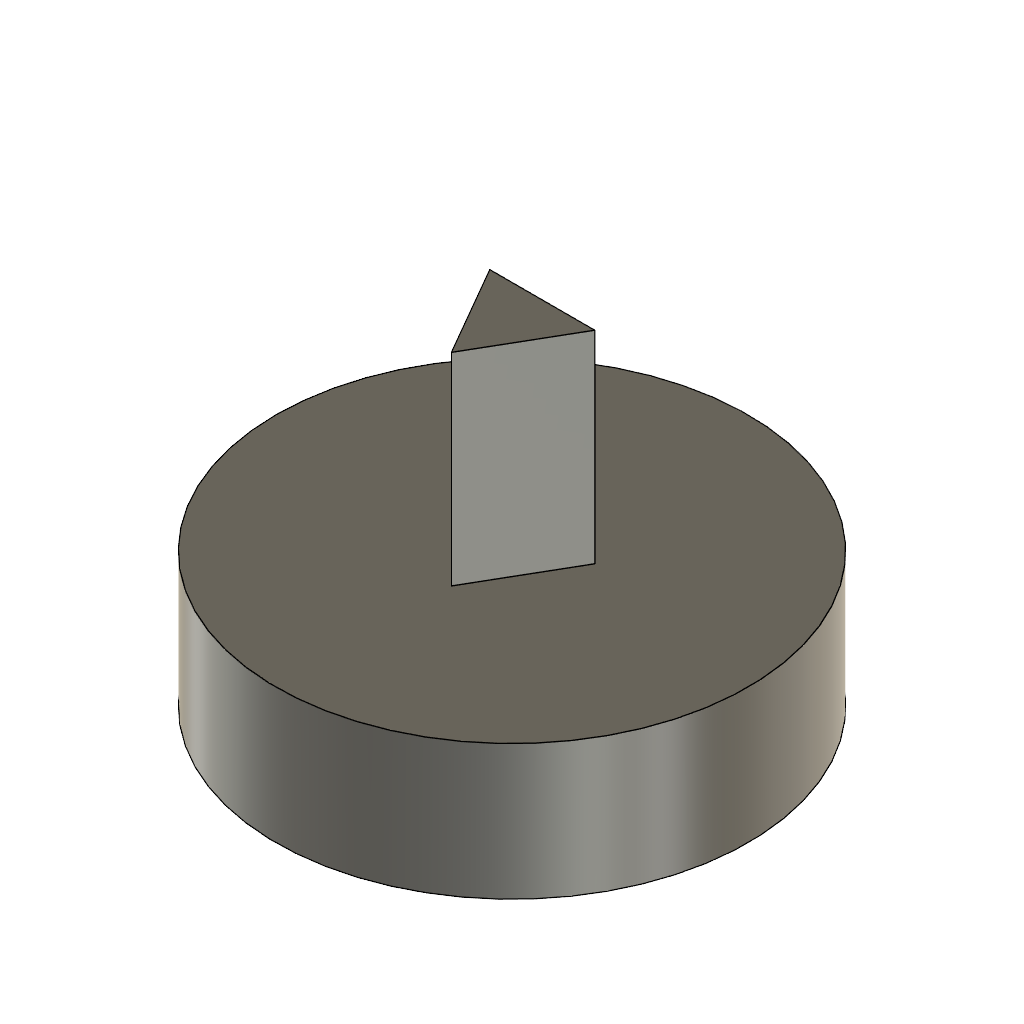
WheelCap (Autodesk Fusion 360 design; units mm, degrees)
part number: 2026-10-10-16-35-32-340
Autodesk Fusion 360 part; units mm, degrees
sketch "Szkic1" plane through (0, 0, 0) normal (0, 0, 1) x (1, 0, 0)
  circle A0 centre (0, 0) radius 3.5
  dimension "d7" = 7
  constraint coincident A0.centre origin
  measures "d7" diameter of A0
extrude "Wyciągnięcie proste1" add sketch "Szkic1" along normal blind 2
sketch "Szkic2" plane through (0, 0, 2) normal (0, 0, 1) x (-1, 0, 0)
  circle A0 centre (0, 0) radius 0.9
  line L0 (0, 0) -> (0, 0.9)
  line L1 (0, 0.9) -> (-0.7796, -0.4497)
  line L2 (0, 0.9) -> (0.7796, -0.4497)
  line L3 (0.7796, -0.4497) -> (-0.7796, -0.4497)
  circle A1 centre (0, 0) radius 3.5
  dimension "d4" = 1.8
  constraint coincident A0.centre L0.start
  constraint coincident A0 L0.end
  constraint vertical L0
  constraint coincident A0 L1.end
  constraint coincident A0 L2.end
  constraint perpendicular L0 L3
  measures "d4" diameter of A0
extrude "Wyciągnięcie proste2" add sketch "Szkic2" along normal blind 3 contours L1 L2 L3
